Autodesk Fusion 360 part; units mm, degrees
(part 3 of 8)
sketch "SW1 support 1 profile" plane through (0, 0, 2) normal (0, 0, 1) x (1, 0, 0)
  line L0 (12.5897, 21.0158) -> (13.5897, 21.0158)
  line L1 (13.5897, 21.0158) -> (13.5897, 24.0158)
  line L2 (13.5897, 24.0158) -> (12.5897, 24.0158)
  line L3 (12.5897, 24.0158) -> (12.5897, 21.0158)
  dimension "d1946" = 12.5897
  dimension "d1947" = 21.0158
  dimension "d1948" = 1
  dimension "d1949" = 3
  constraint horizontal L0
  constraint vertical L1
  constraint horizontal L2
  constraint vertical L3
  measures "d1946" horizontal distance of origin L0.start
  measures "d1947" vertical distance of origin L0.start
  measures "d1948" distance of L0.start L0.end
  measures "d1949" distance of L0.end L1.end
extrude "SW1 support 1" add sketch "SW1 support 1 profile" along normal blind 14.2118 bodies 3
sketch "SW1 support 1 cap profile" plane through (0, -1.1931, 13.6376) normal (0, -0.087156, 0.996195) x (1, 0, 0)
  line L0 (12.4897, 21.7995) -> (13.6897, 21.7995)
  line L1 (13.6897, 21.7995) -> (13.6897, 25.7995)
  line L2 (13.6897, 25.7995) -> (12.4897, 25.7995)
  line L3 (12.4897, 25.7995) -> (12.4897, 21.7995)
  dimension "d1952" = 12.4897
  dimension "d1953" = 21.7995
  dimension "d1954" = 1.2
  dimension "d1955" = 4
  constraint horizontal L0
  constraint vertical L1
  constraint horizontal L2
  constraint vertical L3
  measures "d1952" horizontal distance of origin L0.start
  measures "d1953" vertical distance of origin L0.start
  measures "d1954" distance of L0.start L0.end
  measures "d1955" distance of L0.end L1.end
extrude "SW1 support 1 inclined cap" cut sketch "SW1 support 1 cap profile" along normal blind 39.0612 bodies 3
sketch "SW1 support 2 reinforced stem profile" plane through (0, 0, 2) normal (0, 0, 1) x (1, 0, 0)
  line L0 (16.8897, 20.0158) -> (19.2897, 20.0158)
  line L1 (19.2897, 20.0158) -> (19.2897, 25.0158)
  line L2 (19.2897, 25.0158) -> (16.8897, 25.0158)
  line L3 (16.8897, 25.0158) -> (16.8897, 20.0158)
  dimension "d1958" = 16.8897
  dimension "d1959" = 20.0158
  dimension "d1960" = 2.4
  dimension "d1961" = 5
  constraint horizontal L0
  constraint vertical L1
  constraint horizontal L2
  constraint vertical L3
  measures "d1958" horizontal distance of origin L0.start
  measures "d1959" vertical distance of origin L0.start
  measures "d1960" distance of L0.start L0.end
  measures "d1961" distance of L0.end L1.end
extrude "SW1 support 2 reinforced stem" add sketch "SW1 support 2 reinforced stem profile" along normal blind 11.7118 bodies 3
sketch "SW1 support 2 profile" plane through (0, 0, 2) normal (0, 0, 1) x (1, 0, 0)
  line L0 (17.5897, 21.0158) -> (18.5897, 21.0158)
  line L1 (18.5897, 21.0158) -> (18.5897, 24.0158)
  line L2 (18.5897, 24.0158) -> (17.5897, 24.0158)
  line L3 (17.5897, 24.0158) -> (17.5897, 21.0158)
  dimension "d1964" = 17.5897
  dimension "d1965" = 21.0158
  dimension "d1966" = 1
  dimension "d1967" = 3
  constraint horizontal L0
  constraint vertical L1
  constraint horizontal L2
  constraint vertical L3
  measures "d1964" horizontal distance of origin L0.start
  measures "d1965" vertical distance of origin L0.start
  measures "d1966" distance of L0.start L0.end
  measures "d1967" distance of L0.end L1.end
extrude "SW1 support 2" add sketch "SW1 support 2 profile" along normal blind 14.2118 bodies 3
sketch "SW1 support 2 cap profile" plane through (0, -1.1931, 13.6376) normal (0, -0.087156, 0.996195) x (1, 0, 0)
  line L0 (17.4897, 21.7995) -> (18.6897, 21.7995)
  line L1 (18.6897, 21.7995) -> (18.6897, 25.7995)
  line L2 (18.6897, 25.7995) -> (17.4897, 25.7995)
  line L3 (17.4897, 25.7995) -> (17.4897, 21.7995)
  dimension "d1970" = 17.4897
  dimension "d1971" = 21.7995
  dimension "d1972" = 1.2
  dimension "d1973" = 4
  constraint horizontal L0
  constraint vertical L1
  constraint horizontal L2
  constraint vertical L3
  measures "d1970" horizontal distance of origin L0.start
  measures "d1971" vertical distance of origin L0.start
  measures "d1972" distance of L0.start L0.end
  measures "d1973" distance of L0.end L1.end
extrude "SW1 support 2 inclined cap" cut sketch "SW1 support 2 cap profile" along normal blind 39.0612 bodies 3
sketch "SW2 receiver profile" plane through (0, -2.1431, 24.4961) normal (0, -0.087156, 0.996195) x (1, 0, 0)
  line L0 (30.8, 17.6972) -> (49.2, 17.6972)
  line L1 (49.2, 17.6972) -> (49.2, 35.2972)
  line L2 (49.2, 35.2972) -> (30.8, 35.2972)
  line L3 (30.8, 35.2972) -> (30.8, 17.6972)
  dimension "d1976" = 30.8
  dimension "d1977" = 17.6972
  dimension "d1978" = 18.4
  dimension "d1979" = 17.6
  constraint horizontal L0
  constraint vertical L1
  constraint horizontal L2
  constraint vertical L3
  measures "d1976" horizontal distance of origin L0.start
  measures "d1977" vertical distance of origin L0.start
  measures "d1978" distance of L0.start L0.end
  measures "d1979" distance of L0.end L1.end
extrude "SW2 integrated receiver" add sketch "SW2 receiver profile" against normal blind 11.5 bodies 2
sketch "SW2 switch lower clearance profile" plane through (0, -2.1431, 24.4961) normal (0, -0.087156, 0.996195) x (1, 0, 0)
  line L0 (32, 18.4972) -> (48, 18.4972)
  line L1 (48, 18.4972) -> (48, 34.4972)
  line L2 (48, 34.4972) -> (32, 34.4972)
  line L3 (32, 34.4972) -> (32, 18.4972)
  dimension "d1982" = 32
  dimension "d1983" = 18.4972
  dimension "d1984" = 16
  dimension "d1985" = 16
  constraint horizontal L0
  constraint vertical L1
  constraint horizontal L2
  constraint vertical L3
  measures "d1982" horizontal distance of origin L0.start
  measures "d1983" vertical distance of origin L0.start
  measures "d1984" distance of L0.start L0.end
  measures "d1985" distance of L0.end L1.end
extrude "SW2 switch lower clearance" cut sketch "SW2 switch lower clearance profile" against normal blind 5.5 bodies 2
sketch "SW2 holder pocket profile" plane through (0, -1.6638, 19.017) normal (0, -0.087156, 0.996195) x (1, 0, 0)
  line L0 (34.374, 19.925) -> (45.8055, 19.925)
  line L1 (45.8055, 19.925) -> (45.8055, 30.0741)
  line L2 (45.8055, 30.0741) -> (34.374, 30.0741)
  line L3 (34.374, 30.0741) -> (34.374, 19.925)
  dimension "d1988" = 34.374
  dimension "d1989" = 19.925
  dimension "d1990" = 11.4315
  dimension "d1991" = 10.1491
  constraint horizontal L0
  constraint vertical L1
  constraint horizontal L2
  constraint vertical L3
  measures "d1988" horizontal distance of origin L0.start
  measures "d1989" vertical distance of origin L0.start
  measures "d1990" distance of L0.start L0.end
  measures "d1991" distance of L0.end L1.end
extrude "SW2 open-bottom holder pocket" cut sketch "SW2 holder pocket profile" against normal blind 6.2 bodies 2
sketch "SW2 spring 1 release 1 profile" plane through (0, -2.056, 23.4999) normal (0, -0.087156, 0.996195) x (1, 0, 0)
  line L0 (30.7897, 27.0995) -> (34.374, 27.0995)
  line L1 (34.374, 27.0995) -> (34.374, 27.6995)
  line L2 (34.374, 27.6995) -> (30.7897, 27.6995)
  line L3 (30.7897, 27.6995) -> (30.7897, 27.0995)
  dimension "d1994" = 30.7897
  dimension "d1995" = 27.0995
  dimension "d1996" = 3.5843
  dimension "d1997" = 0.6
  constraint horizontal L0
  constraint vertical L1
  constraint horizontal L2
  constraint vertical L3
  measures "d1994" horizontal distance of origin L0.start
  measures "d1995" vertical distance of origin L0.start
  measures "d1996" distance of L0.start L0.end
  measures "d1997" distance of L0.end L1.end
extrude "SW2 spring 1 release 1" cut sketch "SW2 spring 1 release 1 profile" against normal blind 10.7 bodies 2
sketch "SW2 spring 1 release 2 profile" plane through (0, -2.056, 23.4999) normal (0, -0.087156, 0.996195) x (1, 0, 0)
  line L0 (30.7897, 29.6995) -> (34.374, 29.6995)
  line L1 (34.374, 29.6995) -> (34.374, 30.2995)
  line L2 (34.374, 30.2995) -> (30.7897, 30.2995)
  line L3 (30.7897, 30.2995) -> (30.7897, 29.6995)
  dimension "d2000" = 30.7897
  dimension "d2001" = 29.6995
  dimension "d2002" = 3.5843
  dimension "d2003" = 0.6
  constraint horizontal L0
  constraint vertical L1
  constraint horizontal L2
  constraint vertical L3
  measures "d2000" horizontal distance of origin L0.start
  measures "d2001" vertical distance of origin L0.start
  measures "d2002" distance of L0.start L0.end
  measures "d2003" distance of L0.end L1.end
extrude "SW2 spring 1 release 2" cut sketch "SW2 spring 1 release 2 profile" against normal blind 10.7 bodies 2
sketch "SW2 spring 1 inner clearance profile" plane through (0, -1.6638, 19.017) normal (0, -0.087156, 0.996195) x (1, 0, 0)
  line L0 (31.6897, 27.6995) -> (34.374, 27.6995)
  line L1 (34.374, 27.6995) -> (34.374, 29.6995)
  line L2 (34.374, 29.6995) -> (31.6897, 29.6995)
  line L3 (31.6897, 29.6995) -> (31.6897, 27.6995)
  dimension "d2006" = 31.6897
  dimension "d2007" = 27.6995
  dimension "d2008" = 2.6843
  dimension "d2009" = 2
  constraint horizontal L0
  constraint vertical L1
  constraint horizontal L2
  constraint vertical L3
  measures "d2006" horizontal distance of origin L0.start
  measures "d2007" vertical distance of origin L0.start
  measures "d2008" distance of L0.start L0.end
  measures "d2009" distance of L0.end L1.end
extrude "SW2 spring 1 inner clearance" cut sketch "SW2 spring 1 inner clearance profile" against normal blind 6.2 bodies 2
sketch "SW2 spring 1 hook profile" plane through (0, -1.2106, 13.8368) normal (0, -0.087156, 0.996195) x (1, 0, 0)
  line L0 (30.8897, 27.6995) -> (34.874, 27.6995)
  line L1 (34.874, 27.6995) -> (34.874, 29.6995)
  line L2 (34.874, 29.6995) -> (30.8897, 29.6995)
  line L3 (30.8897, 29.6995) -> (30.8897, 27.6995)
  dimension "d2012" = 30.8897
  dimension "d2013" = 27.6995
  dimension "d2014" = 3.9843
  dimension "d2015" = 2
  constraint horizontal L0
  constraint vertical L1
  constraint horizontal L2
  constraint vertical L3
  measures "d2012" horizontal distance of origin L0.start
  measures "d2013" vertical distance of origin L0.start
  measures "d2014" distance of L0.start L0.end
  measures "d2015" distance of L0.end L1.end
extrude "SW2 spring 1 retaining hook" add sketch "SW2 spring 1 hook profile" against normal blind 0.8 bodies 2
chamfer "SW2 spring 1 45 degree lead-in" distance 0.35 angle 45 1 edges at (34.874, 27.4495, 15.5412) tangent chain off on bodies 2
sketch "SW2 spring 2 release 1 profile" plane through (0, -2.056, 23.4999) normal (0, -0.087156, 0.996195) x (1, 0, 0)
  line L0 (45.8055, 27.0995) -> (49.3897, 27.0995)
  line L1 (49.3897, 27.0995) -> (49.3897, 27.6995)
  line L2 (49.3897, 27.6995) -> (45.8055, 27.6995)
  line L3 (45.8055, 27.6995) -> (45.8055, 27.0995)
  dimension "d2019" = 45.8055
  dimension "d2020" = 27.0995
  dimension "d2021" = 3.5843
  dimension "d2022" = 0.6
  constraint horizontal L0
  constraint vertical L1
  constraint horizontal L2
  constraint vertical L3
  measures "d2019" horizontal distance of origin L0.start
  measures "d2020" vertical distance of origin L0.start
  measures "d2021" distance of L0.start L0.end
  measures "d2022" distance of L0.end L1.end
extrude "SW2 spring 2 release 1" cut sketch "SW2 spring 2 release 1 profile" against normal blind 10.7 bodies 2
sketch "SW2 spring 2 release 2 profile" plane through (0, -2.056, 23.4999) normal (0, -0.087156, 0.996195) x (1, 0, 0)
  line L0 (45.8055, 29.6995) -> (49.3897, 29.6995)
  line L1 (49.3897, 29.6995) -> (49.3897, 30.2995)
  line L2 (49.3897, 30.2995) -> (45.8055, 30.2995)
  line L3 (45.8055, 30.2995) -> (45.8055, 29.6995)
  dimension "d2025" = 45.8055
  dimension "d2026" = 29.6995
  dimension "d2027" = 3.5843
  dimension "d2028" = 0.6
  constraint horizontal L0
  constraint vertical L1
  constraint horizontal L2
  constraint vertical L3
  measures "d2025" horizontal distance of origin L0.start
  measures "d2026" vertical distance of origin L0.start
  measures "d2027" distance of L0.start L0.end
  measures "d2028" distance of L0.end L1.end
extrude "SW2 spring 2 release 2" cut sketch "SW2 spring 2 release 2 profile" against normal blind 10.7 bodies 2
sketch "SW2 spring 2 inner clearance profile" plane through (0, -1.6638, 19.017) normal (0, -0.087156, 0.996195) x (1, 0, 0)
  line L0 (45.8055, 27.6995) -> (48.4897, 27.6995)
  line L1 (48.4897, 27.6995) -> (48.4897, 29.6995)
  line L2 (48.4897, 29.6995) -> (45.8055, 29.6995)
  line L3 (45.8055, 29.6995) -> (45.8055, 27.6995)
  dimension "d2031" = 45.8055
  dimension "d2032" = 27.6995
  dimension "d2033" = 2.6843
  dimension "d2034" = 2
  constraint horizontal L0
  constraint vertical L1
  constraint horizontal L2
  constraint vertical L3
  measures "d2031" horizontal distance of origin L0.start
  measures "d2032" vertical distance of origin L0.start
  measures "d2033" distance of L0.start L0.end
  measures "d2034" distance of L0.end L1.end
extrude "SW2 spring 2 inner clearance" cut sketch "SW2 spring 2 inner clearance profile" against normal blind 6.2 bodies 2
sketch "SW2 spring 2 hook profile" plane through (0, -1.2106, 13.8368) normal (0, -0.087156, 0.996195) x (1, 0, 0)
  line L0 (45.3055, 27.6995) -> (49.2897, 27.6995)
  line L1 (49.2897, 27.6995) -> (49.2897, 29.6995)
  line L2 (49.2897, 29.6995) -> (45.3055, 29.6995)
  line L3 (45.3055, 29.6995) -> (45.3055, 27.6995)
  dimension "d2037" = 45.3055
  dimension "d2038" = 27.6995
  dimension "d2039" = 3.9843
  dimension "d2040" = 2
  constraint horizontal L0
  constraint vertical L1
  constraint horizontal L2
  constraint vertical L3
  measures "d2037" horizontal distance of origin L0.start
  measures "d2038" vertical distance of origin L0.start
  measures "d2039" distance of L0.start L0.end
  measures "d2040" distance of L0.end L1.end
extrude "SW2 spring 2 retaining hook" add sketch "SW2 spring 2 hook profile" against normal blind 0.8 bodies 2
chamfer "SW2 spring 2 45 degree lead-in" distance 0.35 angle 45 1 edges at (45.3055, 27.4495, 15.5412) tangent chain off on bodies 2
sketch "SW2 upper stop 1 profile" plane through (0, -1.6638, 19.017) normal (0, -0.087156, 0.996195) x (1, 0, 0)
  line L0 (36.5897, 28.9995) -> (37.5897, 28.9995)
  line L1 (37.5897, 28.9995) -> (37.5897, 33.7995)
  line L2 (37.5897, 33.7995) -> (36.5897, 33.7995)
  line L3 (36.5897, 33.7995) -> (36.5897, 28.9995)
  dimension "d2044" = 36.5897
  dimension "d2045" = 28.9995
  dimension "d2046" = 1
  dimension "d2047" = 4.8
  constraint horizontal L0
  constraint vertical L1
  constraint horizontal L2
  constraint vertical L3
  measures "d2044" horizontal distance of origin L0.start
  measures "d2045" vertical distance of origin L0.start
  measures "d2046" distance of L0.start L0.end
  measures "d2047" distance of L0.end L1.end
extrude "SW2 upper stop 1" add sketch "SW2 upper stop 1 profile" along normal blind 0.8 bodies 2
sketch "SW2 upper stop 2 profile" plane through (0, -1.6638, 19.017) normal (0, -0.087156, 0.996195) x (1, 0, 0)
  line L0 (42.5897, 28.9995) -> (43.5897, 28.9995)
  line L1 (43.5897, 28.9995) -> (43.5897, 33.7995)
  line L2 (43.5897, 33.7995) -> (42.5897, 33.7995)
  line L3 (42.5897, 33.7995) -> (42.5897, 28.9995)
  dimension "d2050" = 42.5897
  dimension "d2051" = 28.9995
  dimension "d2052" = 1
  dimension "d2053" = 4.8
  constraint horizontal L0
  constraint vertical L1
  constraint horizontal L2
  constraint vertical L3
  measures "d2050" horizontal distance of origin L0.start
  measures "d2051" vertical distance of origin L0.start
  measures "d2052" distance of L0.start L0.end
  measures "d2053" distance of L0.end L1.end
extrude "SW2 upper stop 2" add sketch "SW2 upper stop 2 profile" along normal blind 0.8 bodies 2
sketch "SW2 wire exit 1 profile" plane through (0, -1.5592, 17.8216) normal (0, -0.087156, 0.996195) x (1, 0, 0)
  line L0 (30.7897, 19.8995) -> (34.574, 19.8995)
  line L1 (34.574, 19.8995) -> (34.574, 27.6995)
  line L2 (34.574, 27.6995) -> (30.7897, 27.6995)
  line L3 (30.7897, 27.6995) -> (30.7897, 19.8995)
  dimension "d2056" = 30.7897
  dimension "d2057" = 19.8995
  dimension "d2058" = 3.7843
  dimension "d2059" = 7.8
  constraint horizontal L0
  constraint vertical L1
  constraint horizontal L2
  constraint vertical L3
  measures "d2056" horizontal distance of origin L0.start
  measures "d2057" vertical distance of origin L0.start
  measures "d2058" distance of L0.start L0.end
  measures "d2059" distance of L0.end L1.end
extrude "SW2 wire exit 1" cut sketch "SW2 wire exit 1 profile" against normal blind 5 bodies 2
sketch "SW2 wire exit 2 profile" plane through (0, -1.5592, 17.8216) normal (0, -0.087156, 0.996195) x (1, 0, 0)
  line L0 (45.6055, 19.8995) -> (49.3897, 19.8995)
  line L1 (49.3897, 19.8995) -> (49.3897, 27.6995)
  line L2 (49.3897, 27.6995) -> (45.6055, 27.6995)
  line L3 (45.6055, 27.6995) -> (45.6055, 19.8995)
  dimension "d2062" = 45.6055
  dimension "d2063" = 19.8995
  dimension "d2064" = 3.7843
  dimension "d2065" = 7.8
  constraint horizontal L0
  constraint vertical L1
  constraint horizontal L2
  constraint vertical L3
  measures "d2062" horizontal distance of origin L0.start
  measures "d2063" vertical distance of origin L0.start
  measures "d2064" distance of L0.start L0.end
  measures "d2065" distance of L0.end L1.end
extrude "SW2 wire exit 2" cut sketch "SW2 wire exit 2 profile" against normal blind 5 bodies 2
sketch "SW2 support 1 reinforced stem profile" plane through (0, 0, 2) normal (0, 0, 1) x (1, 0, 0)
  line L0 (36.3897, 20.0158) -> (38.7897, 20.0158)
  line L1 (38.7897, 20.0158) -> (38.7897, 25.0158)
  line L2 (38.7897, 25.0158) -> (36.3897, 25.0158)
  line L3 (36.3897, 25.0158) -> (36.3897, 20.0158)
  dimension "d2068" = 36.3897
  dimension "d2069" = 20.0158
  dimension "d2070" = 2.4
  dimension "d2071" = 5
  constraint horizontal L0
  constraint vertical L1
  constraint horizontal L2
  constraint vertical L3
  measures "d2068" horizontal distance of origin L0.start
  measures "d2069" vertical distance of origin L0.start
  measures "d2070" distance of L0.start L0.end
  measures "d2071" distance of L0.end L1.end
extrude "SW2 support 1 reinforced stem" add sketch "SW2 support 1 reinforced stem profile" along normal blind 11.7118 bodies 3
sketch "SW2 support 1 profile" plane through (0, 0, 2) normal (0, 0, 1) x (1, 0, 0)
  line L0 (37.0897, 21.0158) -> (38.0897, 21.0158)
  line L1 (38.0897, 21.0158) -> (38.0897, 24.0158)
  line L2 (38.0897, 24.0158) -> (37.0897, 24.0158)
  line L3 (37.0897, 24.0158) -> (37.0897, 21.0158)
  dimension "d2074" = 37.0897
  dimension "d2075" = 21.0158
  dimension "d2076" = 1
  dimension "d2077" = 3
  constraint horizontal L0
  constraint vertical L1
  constraint horizontal L2
  constraint vertical L3
  measures "d2074" horizontal distance of origin L0.start
  measures "d2075" vertical distance of origin L0.start
  measures "d2076" distance of L0.start L0.end
  measures "d2077" distance of L0.end L1.end
extrude "SW2 support 1" add sketch "SW2 support 1 profile" along normal blind 14.2118 bodies 3
sketch "SW2 support 1 cap profile" plane through (0, -1.1931, 13.6376) normal (0, -0.087156, 0.996195) x (1, 0, 0)
  line L0 (36.9897, 21.7995) -> (38.1897, 21.7995)
  line L1 (38.1897, 21.7995) -> (38.1897, 25.7995)
  line L2 (38.1897, 25.7995) -> (36.9897, 25.7995)
  line L3 (36.9897, 25.7995) -> (36.9897, 21.7995)
  dimension "d2080" = 36.9897
  dimension "d2081" = 21.7995
  dimension "d2082" = 1.2
  dimension "d2083" = 4
  constraint horizontal L0
  constraint vertical L1
  constraint horizontal L2
  constraint vertical L3
  measures "d2080" horizontal distance of origin L0.start
  measures "d2081" vertical distance of origin L0.start
  measures "d2082" distance of L0.start L0.end
  measures "d2083" distance of L0.end L1.end
extrude "SW2 support 1 inclined cap" cut sketch "SW2 support 1 cap profile" along normal blind 39.0612 bodies 3
sketch "SW2 support 2 reinforced stem profile" plane through (0, 0, 2) normal (0, 0, 1) x (1, 0, 0)
  line L0 (41.3897, 20.0158) -> (43.7897, 20.0158)
  line L1 (43.7897, 20.0158) -> (43.7897, 25.0158)
  line L2 (43.7897, 25.0158) -> (41.3897, 25.0158)
  line L3 (41.3897, 25.0158) -> (41.3897, 20.0158)
  dimension "d2086" = 41.3897
  dimension "d2087" = 20.0158
  dimension "d2088" = 2.4
  dimension "d2089" = 5
  constraint horizontal L0
  constraint vertical L1
  constraint horizontal L2
  constraint vertical L3
  measures "d2086" horizontal distance of origin L0.start
  measures "d2087" vertical distance of origin L0.start
  measures "d2088" distance of L0.start L0.end
  measures "d2089" distance of L0.end L1.end
extrude "SW2 support 2 reinforced stem" add sketch "SW2 support 2 reinforced stem profile" along normal blind 11.7118 bodies 3
sketch "SW2 support 2 profile" plane through (0, 0, 2) normal (0, 0, 1) x (1, 0, 0)
  line L0 (42.0897, 21.0158) -> (43.0897, 21.0158)
  line L1 (43.0897, 21.0158) -> (43.0897, 24.0158)
  line L2 (43.0897, 24.0158) -> (42.0897, 24.0158)
  line L3 (42.0897, 24.0158) -> (42.0897, 21.0158)
  dimension "d2092" = 42.0897
  dimension "d2093" = 21.0158
  dimension "d2094" = 1
  dimension "d2095" = 3
  constraint horizontal L0
  constraint vertical L1
  constraint horizontal L2
  constraint vertical L3
  measures "d2092" horizontal distance of origin L0.start
  measures "d2093" vertical distance of origin L0.start
  measures "d2094" distance of L0.start L0.end
  measures "d2095" distance of L0.end L1.end
extrude "SW2 support 2" add sketch "SW2 support 2 profile" along normal blind 14.2118 bodies 3
sketch "SW2 support 2 cap profile" plane through (0, -1.1931, 13.6376) normal (0, -0.087156, 0.996195) x (1, 0, 0)
  line L0 (41.9897, 21.7995) -> (43.1897, 21.7995)
  line L1 (43.1897, 21.7995) -> (43.1897, 25.7995)
  line L2 (43.1897, 25.7995) -> (41.9897, 25.7995)
  line L3 (41.9897, 25.7995) -> (41.9897, 21.7995)
  dimension "d2098" = 41.9897
  dimension "d2099" = 21.7995
  dimension "d2100" = 1.2
  dimension "d2101" = 4
  constraint horizontal L0
  constraint vertical L1
  constraint horizontal L2
  constraint vertical L3
  measures "d2098" horizontal distance of origin L0.start
  measures "d2099" vertical distance of origin L0.start
  measures "d2100" distance of L0.start L0.end
  measures "d2101" distance of L0.end L1.end
extrude "SW2 support 2 inclined cap" cut sketch "SW2 support 2 cap profile" along normal blind 39.0612 bodies 3
sketch "SW3 receiver profile" plane through (0, -2.1431, 24.4961) normal (0, -0.087156, 0.996195) x (1, 0, 0)
  line L0 (55.3, 17.6972) -> (73.7, 17.6972)
  line L1 (73.7, 17.6972) -> (73.7, 35.2972)
  line L2 (73.7, 35.2972) -> (55.3, 35.2972)
  line L3 (55.3, 35.2972) -> (55.3, 17.6972)
  dimension "d2104" = 55.3
  dimension "d2105" = 17.6972
  dimension "d2106" = 18.4
  dimension "d2107" = 17.6
  constraint horizontal L0
  constraint vertical L1
  constraint horizontal L2
  constraint vertical L3
  measures "d2104" horizontal distance of origin L0.start
  measures "d2105" vertical distance of origin L0.start
  measures "d2106" distance of L0.start L0.end
  measures "d2107" distance of L0.end L1.end
extrude "SW3 integrated receiver" add sketch "SW3 receiver profile" against normal blind 11.5 bodies 2
sketch "SW3 switch lower clearance profile" plane through (0, -2.1431, 24.4961) normal (0, -0.087156, 0.996195) x (1, 0, 0)
  line L0 (56.5, 18.4972) -> (72.5, 18.4972)
  line L1 (72.5, 18.4972) -> (72.5, 34.4972)
  line L2 (72.5, 34.4972) -> (56.5, 34.4972)
  line L3 (56.5, 34.4972) -> (56.5, 18.4972)
  dimension "d2110" = 56.5
  dimension "d2111" = 18.4972
  dimension "d2112" = 16
  dimension "d2113" = 16
  constraint horizontal L0
  constraint vertical L1
  constraint horizontal L2
  constraint vertical L3
  measures "d2110" horizontal distance of origin L0.start
  measures "d2111" vertical distance of origin L0.start
  measures "d2112" distance of L0.start L0.end
  measures "d2113" distance of L0.end L1.end
extrude "SW3 switch lower clearance" cut sketch "SW3 switch lower clearance profile" against normal blind 5.5 bodies 2
sketch "SW3 holder pocket profile" plane through (0, -1.6638, 19.017) normal (0, -0.087156, 0.996195) x (1, 0, 0)
  line L0 (58.874, 19.925) -> (70.3055, 19.925)
  line L1 (70.3055, 19.925) -> (70.3055, 30.0741)
  line L2 (70.3055, 30.0741) -> (58.874, 30.0741)
  line L3 (58.874, 30.0741) -> (58.874, 19.925)
  dimension "d2116" = 58.874
  dimension "d2117" = 19.925
  dimension "d2118" = 11.4315
  dimension "d2119" = 10.1491
  constraint horizontal L0
  constraint vertical L1
  constraint horizontal L2
  constraint vertical L3
  measures "d2116" horizontal distance of origin L0.start
  measures "d2117" vertical distance of origin L0.start
  measures "d2118" distance of L0.start L0.end
  measures "d2119" distance of L0.end L1.end
extrude "SW3 open-bottom holder pocket" cut sketch "SW3 holder pocket profile" against normal blind 6.2 bodies 2
sketch "SW3 spring 1 release 1 profile" plane through (0, -2.056, 23.4999) normal (0, -0.087156, 0.996195) x (1, 0, 0)
  line L0 (55.2897, 27.0995) -> (58.874, 27.0995)
  line L1 (58.874, 27.0995) -> (58.874, 27.6995)
  line L2 (58.874, 27.6995) -> (55.2897, 27.6995)
  line L3 (55.2897, 27.6995) -> (55.2897, 27.0995)
  dimension "d2122" = 55.2897
  dimension "d2123" = 27.0995
  dimension "d2124" = 3.5843
  dimension "d2125" = 0.6
  constraint horizontal L0
  constraint vertical L1
  constraint horizontal L2
  constraint vertical L3
  measures "d2122" horizontal distance of origin L0.start
  measures "d2123" vertical distance of origin L0.start
  measures "d2124" distance of L0.start L0.end
  measures "d2125" distance of L0.end L1.end
extrude "SW3 spring 1 release 1" cut sketch "SW3 spring 1 release 1 profile" against normal blind 10.7 bodies 2
sketch "SW3 spring 1 release 2 profile" plane through (0, -2.056, 23.4999) normal (0, -0.087156, 0.996195) x (1, 0, 0)
  line L0 (55.2897, 29.6995) -> (58.874, 29.6995)
  line L1 (58.874, 29.6995) -> (58.874, 30.2995)
  line L2 (58.874, 30.2995) -> (55.2897, 30.2995)
  line L3 (55.2897, 30.2995) -> (55.2897, 29.6995)
  dimension "d2128" = 55.2897
  dimension "d2129" = 29.6995
  dimension "d2130" = 3.5843
  dimension "d2131" = 0.6
  constraint horizontal L0
  constraint vertical L1
  constraint horizontal L2
  constraint vertical L3
  measures "d2128" horizontal distance of origin L0.start
  measures "d2129" vertical distance of origin L0.start
  measures "d2130" distance of L0.start L0.end
  measures "d2131" distance of L0.end L1.end
extrude "SW3 spring 1 release 2" cut sketch "SW3 spring 1 release 2 profile" against normal blind 10.7 bodies 2
sketch "SW3 spring 1 inner clearance profile" plane through (0, -1.6638, 19.017) normal (0, -0.087156, 0.996195) x (1, 0, 0)
  line L0 (56.1897, 27.6995) -> (58.874, 27.6995)
  line L1 (58.874, 27.6995) -> (58.874, 29.6995)
  line L2 (58.874, 29.6995) -> (56.1897, 29.6995)
  line L3 (56.1897, 29.6995) -> (56.1897, 27.6995)
  dimension "d2134" = 56.1897
  dimension "d2135" = 27.6995
  dimension "d2136" = 2.6843
  dimension "d2137" = 2
  constraint horizontal L0
  constraint vertical L1
  constraint horizontal L2
  constraint vertical L3
  measures "d2134" horizontal distance of origin L0.start
  measures "d2135" vertical distance of origin L0.start
  measures "d2136" distance of L0.start L0.end
  measures "d2137" distance of L0.end L1.end
extrude "SW3 spring 1 inner clearance" cut sketch "SW3 spring 1 inner clearance profile" against normal blind 6.2 bodies 2
sketch "SW3 spring 1 hook profile" plane through (0, -1.2106, 13.8368) normal (0, -0.087156, 0.996195) x (1, 0, 0)
  line L0 (55.3897, 27.6995) -> (59.374, 27.6995)
  line L1 (59.374, 27.6995) -> (59.374, 29.6995)
  line L2 (59.374, 29.6995) -> (55.3897, 29.6995)
  line L3 (55.3897, 29.6995) -> (55.3897, 27.6995)
  dimension "d2140" = 55.3897
  dimension "d2141" = 27.6995
  dimension "d2142" = 3.9843
  dimension "d2143" = 2
  constraint horizontal L0
  constraint vertical L1
  constraint horizontal L2
  constraint vertical L3
  measures "d2140" horizontal distance of origin L0.start
  measures "d2141" vertical distance of origin L0.start
  measures "d2142" distance of L0.start L0.end
  measures "d2143" distance of L0.end L1.end
extrude "SW3 spring 1 retaining hook" add sketch "SW3 spring 1 hook profile" against normal blind 0.8 bodies 2
chamfer "SW3 spring 1 45 degree lead-in" distance 0.35 angle 45 1 edges at (59.374, 27.4495, 15.5412) tangent chain off on bodies 2
sketch "SW3 spring 2 release 1 profile" plane through (0, -2.056, 23.4999) normal (0, -0.087156, 0.996195) x (1, 0, 0)
  line L0 (70.3055, 27.0995) -> (73.8897, 27.0995)
  line L1 (73.8897, 27.0995) -> (73.8897, 27.6995)
  line L2 (73.8897, 27.6995) -> (70.3055, 27.6995)
  line L3 (70.3055, 27.6995) -> (70.3055, 27.0995)
  dimension "d2147" = 70.3055
  dimension "d2148" = 27.0995
  dimension "d2149" = 3.5843
  dimension "d2150" = 0.6
  constraint horizontal L0
  constraint vertical L1
  constraint horizontal L2
  constraint vertical L3
  measures "d2147" horizontal distance of origin L0.start
  measures "d2148" vertical distance of origin L0.start
  measures "d2149" distance of L0.start L0.end
  measures "d2150" distance of L0.end L1.end
extrude "SW3 spring 2 release 1" cut sketch "SW3 spring 2 release 1 profile" against normal blind 10.7 bodies 2
sketch "SW3 spring 2 release 2 profile" plane through (0, -2.056, 23.4999) normal (0, -0.087156, 0.996195) x (1, 0, 0)
  line L0 (70.3055, 29.6995) -> (73.8897, 29.6995)
  line L1 (73.8897, 29.6995) -> (73.8897, 30.2995)
  line L2 (73.8897, 30.2995) -> (70.3055, 30.2995)
  line L3 (70.3055, 30.2995) -> (70.3055, 29.6995)
  dimension "d2153" = 70.3055
  dimension "d2154" = 29.6995
  dimension "d2155" = 3.5843
  dimension "d2156" = 0.6
  constraint horizontal L0
  constraint vertical L1
  constraint horizontal L2
  constraint vertical L3
  measures "d2153" horizontal distance of origin L0.start
  measures "d2154" vertical distance of origin L0.start
  measures "d2155" distance of L0.start L0.end
  measures "d2156" distance of L0.end L1.end
extrude "SW3 spring 2 release 2" cut sketch "SW3 spring 2 release 2 profile" against normal blind 10.7 bodies 2
sketch "SW3 spring 2 inner clearance profile" plane through (0, -1.6638, 19.017) normal (0, -0.087156, 0.996195) x (1, 0, 0)
  line L0 (70.3055, 27.6995) -> (72.9897, 27.6995)
  line L1 (72.9897, 27.6995) -> (72.9897, 29.6995)
  line L2 (72.9897, 29.6995) -> (70.3055, 29.6995)
  line L3 (70.3055, 29.6995) -> (70.3055, 27.6995)
  dimension "d2159" = 70.3055
  dimension "d2160" = 27.6995
  dimension "d2161" = 2.6843
  dimension "d2162" = 2
  constraint horizontal L0
  constraint vertical L1
  constraint horizontal L2
  constraint vertical L3
  measures "d2159" horizontal distance of origin L0.start
  measures "d2160" vertical distance of origin L0.start
  measures "d2161" distance of L0.start L0.end
  measures "d2162" distance of L0.end L1.end
extrude "SW3 spring 2 inner clearance" cut sketch "SW3 spring 2 inner clearance profile" against normal blind 6.2 bodies 2
sketch "SW3 spring 2 hook profile" plane through (0, -1.2106, 13.8368) normal (0, -0.087156, 0.996195) x (1, 0, 0)
  line L0 (69.8055, 27.6995) -> (73.7897, 27.6995)
  line L1 (73.7897, 27.6995) -> (73.7897, 29.6995)
  line L2 (73.7897, 29.6995) -> (69.8055, 29.6995)
  line L3 (69.8055, 29.6995) -> (69.8055, 27.6995)
  dimension "d2165" = 69.8055
  dimension "d2166" = 27.6995
  dimension "d2167" = 3.9843
  dimension "d2168" = 2
  constraint horizontal L0
  constraint vertical L1
  constraint horizontal L2
  constraint vertical L3
  measures "d2165" horizontal distance of origin L0.start
  measures "d2166" vertical distance of origin L0.start
  measures "d2167" distance of L0.start L0.end
  measures "d2168" distance of L0.end L1.end
extrude "SW3 spring 2 retaining hook" add sketch "SW3 spring 2 hook profile" against normal blind 0.8 bodies 2
chamfer "SW3 spring 2 45 degree lead-in" distance 0.35 angle 45 1 edges at (69.8055, 27.4495, 15.5412) tangent chain off on bodies 2
sketch "SW3 upper stop 1 profile" plane through (0, -1.6638, 19.017) normal (0, -0.087156, 0.996195) x (1, 0, 0)
  line L0 (61.0897, 28.9995) -> (62.0897, 28.9995)
  line L1 (62.0897, 28.9995) -> (62.0897, 33.7995)
  line L2 (62.0897, 33.7995) -> (61.0897, 33.7995)
  line L3 (61.0897, 33.7995) -> (61.0897, 28.9995)
  dimension "d2172" = 61.0897
  dimension "d2173" = 28.9995
  dimension "d2174" = 1
  dimension "d2175" = 4.8
  constraint horizontal L0
  constraint vertical L1
  constraint horizontal L2
  constraint vertical L3
  measures "d2172" horizontal distance of origin L0.start
  measures "d2173" vertical distance of origin L0.start
  measures "d2174" distance of L0.start L0.end
  measures "d2175" distance of L0.end L1.end
extrude "SW3 upper stop 1" add sketch "SW3 upper stop 1 profile" along normal blind 0.8 bodies 2
sketch "SW3 upper stop 2 profile" plane through (0, -1.6638, 19.017) normal (0, -0.087156, 0.996195) x (1, 0, 0)
  line L0 (67.0897, 28.9995) -> (68.0897, 28.9995)
  line L1 (68.0897, 28.9995) -> (68.0897, 33.7995)
  line L2 (68.0897, 33.7995) -> (67.0897, 33.7995)
  line L3 (67.0897, 33.7995) -> (67.0897, 28.9995)
  dimension "d2178" = 67.0897
  dimension "d2179" = 28.9995
  dimension "d2180" = 1
  dimension "d2181" = 4.8
  constraint horizontal L0
  constraint vertical L1
  constraint horizontal L2
  constraint vertical L3
  measures "d2178" horizontal distance of origin L0.start
  measures "d2179" vertical distance of origin L0.start
  measures "d2180" distance of L0.start L0.end
  measures "d2181" distance of L0.end L1.end
extrude "SW3 upper stop 2" add sketch "SW3 upper stop 2 profile" along normal blind 0.8 bodies 2
sketch "SW3 wire exit 1 profile" plane through (0, -1.5592, 17.8216) normal (0, -0.087156, 0.996195) x (1, 0, 0)
  line L0 (55.2897, 19.8995) -> (59.074, 19.8995)
  line L1 (59.074, 19.8995) -> (59.074, 27.6995)
  line L2 (59.074, 27.6995) -> (55.2897, 27.6995)
  line L3 (55.2897, 27.6995) -> (55.2897, 19.8995)
  dimension "d2184" = 55.2897
  dimension "d2185" = 19.8995
  dimension "d2186" = 3.7843
  dimension "d2187" = 7.8
  constraint horizontal L0
  constraint vertical L1
  constraint horizontal L2
  constraint vertical L3
  measures "d2184" horizontal distance of origin L0.start
  measures "d2185" vertical distance of origin L0.start
  measures "d2186" distance of L0.start L0.end
  measures "d2187" distance of L0.end L1.end
extrude "SW3 wire exit 1" cut sketch "SW3 wire exit 1 profile" against normal blind 5 bodies 2
sketch "SW3 wire exit 2 profile" plane through (0, -1.5592, 17.8216) normal (0, -0.087156, 0.996195) x (1, 0, 0)
  line L0 (70.1055, 19.8995) -> (73.8897, 19.8995)
  line L1 (73.8897, 19.8995) -> (73.8897, 27.6995)
  line L2 (73.8897, 27.6995) -> (70.1055, 27.6995)
  line L3 (70.1055, 27.6995) -> (70.1055, 19.8995)
  dimension "d2190" = 70.1055
  dimension "d2191" = 19.8995
  dimension "d2192" = 3.7843
  dimension "d2193" = 7.8
  constraint horizontal L0
  constraint vertical L1
  constraint horizontal L2
  constraint vertical L3
  measures "d2190" horizontal distance of origin L0.start
  measures "d2191" vertical distance of origin L0.start
  measures "d2192" distance of L0.start L0.end
  measures "d2193" distance of L0.end L1.end
extrude "SW3 wire exit 2" cut sketch "SW3 wire exit 2 profile" against normal blind 5 bodies 2
sketch "SW3 support 1 reinforced stem profile" plane through (0, 0, 2) normal (0, 0, 1) x (1, 0, 0)
  line L0 (60.8897, 20.0158) -> (63.2897, 20.0158)
  line L1 (63.2897, 20.0158) -> (63.2897, 25.0158)
  line L2 (63.2897, 25.0158) -> (60.8897, 25.0158)
  line L3 (60.8897, 25.0158) -> (60.8897, 20.0158)
  dimension "d2196" = 60.8897
  dimension "d2197" = 20.0158
  dimension "d2198" = 2.4
  dimension "d2199" = 5
  constraint horizontal L0
  constraint vertical L1
  constraint horizontal L2
  constraint vertical L3
  measures "d2196" horizontal distance of origin L0.start
  measures "d2197" vertical distance of origin L0.start
  measures "d2198" distance of L0.start L0.end
  measures "d2199" distance of L0.end L1.end
extrude "SW3 support 1 reinforced stem" add sketch "SW3 support 1 reinforced stem profile" along normal blind 11.7118 bodies 3
sketch "SW3 support 1 profile" plane through (0, 0, 2) normal (0, 0, 1) x (1, 0, 0)
  line L0 (61.5897, 21.0158) -> (62.5897, 21.0158)
  line L1 (62.5897, 21.0158) -> (62.5897, 24.0158)
  line L2 (62.5897, 24.0158) -> (61.5897, 24.0158)
  line L3 (61.5897, 24.0158) -> (61.5897, 21.0158)
  dimension "d2202" = 61.5897
  dimension "d2203" = 21.0158
  dimension "d2204" = 1
  dimension "d2205" = 3
  constraint horizontal L0
  constraint vertical L1
  constraint horizontal L2
  constraint vertical L3
  measures "d2202" horizontal distance of origin L0.start
  measures "d2203" vertical distance of origin L0.start
  measures "d2204" distance of L0.start L0.end
  measures "d2205" distance of L0.end L1.end
extrude "SW3 support 1" add sketch "SW3 support 1 profile" along normal blind 14.2118 bodies 3
sketch "SW3 support 1 cap profile" plane through (0, -1.1931, 13.6376) normal (0, -0.087156, 0.996195) x (1, 0, 0)
  line L0 (61.4897, 21.7995) -> (62.6897, 21.7995)
  line L1 (62.6897, 21.7995) -> (62.6897, 25.7995)
  line L2 (62.6897, 25.7995) -> (61.4897, 25.7995)
  line L3 (61.4897, 25.7995) -> (61.4897, 21.7995)
  dimension "d2208" = 61.4897
  dimension "d2209" = 21.7995
  dimension "d2210" = 1.2
  dimension "d2211" = 4
  constraint horizontal L0
  constraint vertical L1
  constraint horizontal L2
  constraint vertical L3
  measures "d2208" horizontal distance of origin L0.start
  measures "d2209" vertical distance of origin L0.start
  measures "d2210" distance of L0.start L0.end
  measures "d2211" distance of L0.end L1.end
extrude "SW3 support 1 inclined cap" cut sketch "SW3 support 1 cap profile" along normal blind 39.0612 bodies 3
sketch "SW3 support 2 reinforced stem profile" plane through (0, 0, 2) normal (0, 0, 1) x (1, 0, 0)
  line L0 (65.8897, 20.0158) -> (68.2897, 20.0158)
  line L1 (68.2897, 20.0158) -> (68.2897, 25.0158)
  line L2 (68.2897, 25.0158) -> (65.8897, 25.0158)
  line L3 (65.8897, 25.0158) -> (65.8897, 20.0158)
  dimension "d2214" = 65.8897
  dimension "d2215" = 20.0158
  dimension "d2216" = 2.4
  dimension "d2217" = 5
  constraint horizontal L0
  constraint vertical L1
  constraint horizontal L2
  constraint vertical L3
  measures "d2214" horizontal distance of origin L0.start
  measures "d2215" vertical distance of origin L0.start
  measures "d2216" distance of L0.start L0.end
  measures "d2217" distance of L0.end L1.end
extrude "SW3 support 2 reinforced stem" add sketch "SW3 support 2 reinforced stem profile" along normal blind 11.7118 bodies 3
sketch "SW3 support 2 profile" plane through (0, 0, 2) normal (0, 0, 1) x (1, 0, 0)
  line L0 (66.5897, 21.0158) -> (67.5897, 21.0158)
  line L1 (67.5897, 21.0158) -> (67.5897, 24.0158)
  line L2 (67.5897, 24.0158) -> (66.5897, 24.0158)
  line L3 (66.5897, 24.0158) -> (66.5897, 21.0158)
  dimension "d2220" = 66.5897
  dimension "d2221" = 21.0158
  dimension "d2222" = 1
  dimension "d2223" = 3
  constraint horizontal L0
  constraint vertical L1
  constraint horizontal L2
  constraint vertical L3
  measures "d2220" horizontal distance of origin L0.start
  measures "d2221" vertical distance of origin L0.start
  measures "d2222" distance of L0.start L0.end
  measures "d2223" distance of L0.end L1.end
extrude "SW3 support 2" add sketch "SW3 support 2 profile" along normal blind 14.2118 bodies 3
sketch "SW3 support 2 cap profile" plane through (0, -1.1931, 13.6376) normal (0, -0.087156, 0.996195) x (1, 0, 0)
  line L0 (66.4897, 21.7995) -> (67.6897, 21.7995)
  line L1 (67.6897, 21.7995) -> (67.6897, 25.7995)
  line L2 (67.6897, 25.7995) -> (66.4897, 25.7995)
  line L3 (66.4897, 25.7995) -> (66.4897, 21.7995)
  dimension "d2226" = 66.4897
  dimension "d2227" = 21.7995
  dimension "d2228" = 1.2
  dimension "d2229" = 4
  constraint horizontal L0
  constraint vertical L1
  constraint horizontal L2
  constraint vertical L3
  measures "d2226" horizontal distance of origin L0.start
  measures "d2227" vertical distance of origin L0.start
  measures "d2228" distance of L0.start L0.end
  measures "d2229" distance of L0.end L1.end
extrude "SW3 support 2 inclined cap" cut sketch "SW3 support 2 cap profile" along normal blind 39.0612 bodies 3
sketch "SW4 receiver profile" plane through (0, -2.1431, 24.4961) normal (0, -0.087156, 0.996195) x (1, 0, 0)
  line L0 (6.3, 42.1972) -> (24.7, 42.1972)
  line L1 (24.7, 42.1972) -> (24.7, 59.7972)
  line L2 (24.7, 59.7972) -> (6.3, 59.7972)
  line L3 (6.3, 59.7972) -> (6.3, 42.1972)
  dimension "d2232" = 6.3
  dimension "d2233" = 42.1972
  dimension "d2234" = 18.4
  dimension "d2235" = 17.6
  constraint horizontal L0
  constraint vertical L1
  constraint horizontal L2
  constraint vertical L3
  measures "d2232" horizontal distance of origin L0.start
  measures "d2233" vertical distance of origin L0.start
  measures "d2234" distance of L0.start L0.end
  measures "d2235" distance of L0.end L1.end
extrude "SW4 integrated receiver" add sketch "SW4 receiver profile" against normal blind 11.5 bodies 2
sketch "SW4 switch lower clearance profile" plane through (0, -2.1431, 24.4961) normal (0, -0.087156, 0.996195) x (1, 0, 0)
  line L0 (7.5, 42.9972) -> (23.5, 42.9972)
  line L1 (23.5, 42.9972) -> (23.5, 58.9972)
  line L2 (23.5, 58.9972) -> (7.5, 58.9972)
  line L3 (7.5, 58.9972) -> (7.5, 42.9972)
  dimension "d2238" = 7.5
  dimension "d2239" = 42.9972
  dimension "d2240" = 16
  dimension "d2241" = 16
  constraint horizontal L0
  constraint vertical L1
  constraint horizontal L2
  constraint vertical L3
  measures "d2238" horizontal distance of origin L0.start
  measures "d2239" vertical distance of origin L0.start
  measures "d2240" distance of L0.start L0.end
  measures "d2241" distance of L0.end L1.end
extrude "SW4 switch lower clearance" cut sketch "SW4 switch lower clearance profile" against normal blind 5.5 bodies 2
sketch "SW4 holder pocket profile" plane through (0, -1.6638, 19.017) normal (0, -0.087156, 0.996195) x (1, 0, 0)
  line L0 (9.874, 44.425) -> (21.3055, 44.425)
  line L1 (21.3055, 44.425) -> (21.3055, 54.5741)
  line L2 (21.3055, 54.5741) -> (9.874, 54.5741)
  line L3 (9.874, 54.5741) -> (9.874, 44.425)
  dimension "d2244" = 9.874
  dimension "d2245" = 44.425
  dimension "d2246" = 11.4315
  dimension "d2247" = 10.1491
  constraint horizontal L0
  constraint vertical L1
  constraint horizontal L2
  constraint vertical L3
  measures "d2244" horizontal distance of origin L0.start
  measures "d2245" vertical distance of origin L0.start
  measures "d2246" distance of L0.start L0.end
  measures "d2247" distance of L0.end L1.end
extrude "SW4 open-bottom holder pocket" cut sketch "SW4 holder pocket profile" against normal blind 6.2 bodies 2
sketch "SW4 spring 1 release 1 profile" plane through (0, -2.056, 23.4999) normal (0, -0.087156, 0.996195) x (1, 0, 0)
  line L0 (6.2897, 51.5995) -> (9.874, 51.5995)
  line L1 (9.874, 51.5995) -> (9.874, 52.1995)
  line L2 (9.874, 52.1995) -> (6.2897, 52.1995)
  line L3 (6.2897, 52.1995) -> (6.2897, 51.5995)
  dimension "d2250" = 6.2897
  dimension "d2251" = 51.5995
  dimension "d2252" = 3.5843
  dimension "d2253" = 0.6
  constraint horizontal L0
  constraint vertical L1
  constraint horizontal L2
  constraint vertical L3
  measures "d2250" horizontal distance of origin L0.start
  measures "d2251" vertical distance of origin L0.start
  measures "d2252" distance of L0.start L0.end
  measures "d2253" distance of L0.end L1.end
extrude "SW4 spring 1 release 1" cut sketch "SW4 spring 1 release 1 profile" against normal blind 10.7 bodies 2
sketch "SW4 spring 1 release 2 profile" plane through (0, -2.056, 23.4999) normal (0, -0.087156, 0.996195) x (1, 0, 0)
  line L0 (6.2897, 54.1995) -> (9.874, 54.1995)
  line L1 (9.874, 54.1995) -> (9.874, 54.7995)
  line L2 (9.874, 54.7995) -> (6.2897, 54.7995)
  line L3 (6.2897, 54.7995) -> (6.2897, 54.1995)
  dimension "d2256" = 6.2897
  dimension "d2257" = 54.1995
  dimension "d2258" = 3.5843
  dimension "d2259" = 0.6
  constraint horizontal L0
  constraint vertical L1
  constraint horizontal L2
  constraint vertical L3
  measures "d2256" horizontal distance of origin L0.start
  measures "d2257" vertical distance of origin L0.start
  measures "d2258" distance of L0.start L0.end
  measures "d2259" distance of L0.end L1.end
extrude "SW4 spring 1 release 2" cut sketch "SW4 spring 1 release 2 profile" against normal blind 10.7 bodies 2
sketch "SW4 spring 1 inner clearance profile" plane through (0, -1.6638, 19.017) normal (0, -0.087156, 0.996195) x (1, 0, 0)
  line L0 (7.1897, 52.1995) -> (9.874, 52.1995)
  line L1 (9.874, 52.1995) -> (9.874, 54.1995)
  line L2 (9.874, 54.1995) -> (7.1897, 54.1995)
  line L3 (7.1897, 54.1995) -> (7.1897, 52.1995)
  dimension "d2262" = 7.1897
  dimension "d2263" = 52.1995
  dimension "d2264" = 2.6843
  dimension "d2265" = 2
  constraint horizontal L0
  constraint vertical L1
  constraint horizontal L2
  constraint vertical L3
  measures "d2262" horizontal distance of origin L0.start
  measures "d2263" vertical distance of origin L0.start
  measures "d2264" distance of L0.start L0.end
  measures "d2265" distance of L0.end L1.end
extrude "SW4 spring 1 inner clearance" cut sketch "SW4 spring 1 inner clearance profile" against normal blind 6.2 bodies 2
sketch "SW4 spring 1 hook profile" plane through (0, -1.2106, 13.8368) normal (0, -0.087156, 0.996195) x (1, 0, 0)
  line L0 (6.3897, 52.1995) -> (10.374, 52.1995)
  line L1 (10.374, 52.1995) -> (10.374, 54.1995)
  line L2 (10.374, 54.1995) -> (6.3897, 54.1995)
  line L3 (6.3897, 54.1995) -> (6.3897, 52.1995)
  dimension "d2268" = 6.3897
  dimension "d2269" = 52.1995
  dimension "d2270" = 3.9843
  dimension "d2271" = 2
  constraint horizontal L0
  constraint vertical L1
  constraint horizontal L2
  constraint vertical L3
  measures "d2268" horizontal distance of origin L0.start
  measures "d2269" vertical distance of origin L0.start
  measures "d2270" distance of L0.start L0.end
  measures "d2271" distance of L0.end L1.end
extrude "SW4 spring 1 retaining hook" add sketch "SW4 spring 1 hook profile" against normal blind 0.8 bodies 2
chamfer "SW4 spring 1 45 degree lead-in" distance 0.35 angle 45 1 edges at (10.374, 51.8562, 17.6765) tangent chain off on bodies 2
sketch "SW4 spring 2 release 1 profile" plane through (0, -2.056, 23.4999) normal (0, -0.087156, 0.996195) x (1, 0, 0)
  line L0 (21.3055, 51.5995) -> (24.8897, 51.5995)
  line L1 (24.8897, 51.5995) -> (24.8897, 52.1995)
  line L2 (24.8897, 52.1995) -> (21.3055, 52.1995)
  line L3 (21.3055, 52.1995) -> (21.3055, 51.5995)
  dimension "d2275" = 21.3055
  dimension "d2276" = 51.5995
  dimension "d2277" = 3.5843
  dimension "d2278" = 0.6
  constraint horizontal L0
  constraint vertical L1
  constraint horizontal L2
  constraint vertical L3
  measures "d2275" horizontal distance of origin L0.start
  measures "d2276" vertical distance of origin L0.start
  measures "d2277" distance of L0.start L0.end
  measures "d2278" distance of L0.end L1.end
extrude "SW4 spring 2 release 1" cut sketch "SW4 spring 2 release 1 profile" against normal blind 10.7 bodies 2
sketch "SW4 spring 2 release 2 profile" plane through (0, -2.056, 23.4999) normal (0, -0.087156, 0.996195) x (1, 0, 0)
  line L0 (21.3055, 54.1995) -> (24.8897, 54.1995)
  line L1 (24.8897, 54.1995) -> (24.8897, 54.7995)
  line L2 (24.8897, 54.7995) -> (21.3055, 54.7995)
  line L3 (21.3055, 54.7995) -> (21.3055, 54.1995)
  dimension "d2281" = 21.3055
  dimension "d2282" = 54.1995
  dimension "d2283" = 3.5843
  dimension "d2284" = 0.6
  constraint horizontal L0
  constraint vertical L1
  constraint horizontal L2
  constraint vertical L3
  measures "d2281" horizontal distance of origin L0.start
  measures "d2282" vertical distance of origin L0.start
  measures "d2283" distance of L0.start L0.end
  measures "d2284" distance of L0.end L1.end
extrude "SW4 spring 2 release 2" cut sketch "SW4 spring 2 release 2 profile" against normal blind 10.7 bodies 2
sketch "SW4 spring 2 inner clearance profile" plane through (0, -1.6638, 19.017) normal (0, -0.087156, 0.996195) x (1, 0, 0)
  line L0 (21.3055, 52.1995) -> (23.9897, 52.1995)
  line L1 (23.9897, 52.1995) -> (23.9897, 54.1995)
  line L2 (23.9897, 54.1995) -> (21.3055, 54.1995)
  line L3 (21.3055, 54.1995) -> (21.3055, 52.1995)
  dimension "d2287" = 21.3055
  dimension "d2288" = 52.1995
  dimension "d2289" = 2.6843
  dimension "d2290" = 2
  constraint horizontal L0
  constraint vertical L1
  constraint horizontal L2
  constraint vertical L3
  measures "d2287" horizontal distance of origin L0.start
  measures "d2288" vertical distance of origin L0.start
  measures "d2289" distance of L0.start L0.end
  measures "d2290" distance of L0.end L1.end
extrude "SW4 spring 2 inner clearance" cut sketch "SW4 spring 2 inner clearance profile" against normal blind 6.2 bodies 2
sketch "SW4 spring 2 hook profile" plane through (0, -1.2106, 13.8368) normal (0, -0.087156, 0.996195) x (1, 0, 0)
  line L0 (20.8055, 52.1995) -> (24.7897, 52.1995)
  line L1 (24.7897, 52.1995) -> (24.7897, 54.1995)
  line L2 (24.7897, 54.1995) -> (20.8055, 54.1995)
  line L3 (20.8055, 54.1995) -> (20.8055, 52.1995)
  dimension "d2293" = 20.8055
  dimension "d2294" = 52.1995
  dimension "d2295" = 3.9843
  dimension "d2296" = 2
  constraint horizontal L0
  constraint vertical L1
  constraint horizontal L2
  constraint vertical L3
  measures "d2293" horizontal distance of origin L0.start
  measures "d2294" vertical distance of origin L0.start
  measures "d2295" distance of L0.start L0.end
  measures "d2296" distance of L0.end L1.end
extrude "SW4 spring 2 retaining hook" add sketch "SW4 spring 2 hook profile" against normal blind 0.8 bodies 2
chamfer "SW4 spring 2 45 degree lead-in" distance 0.35 angle 45 1 edges at (20.8055, 51.8562, 17.6765) tangent chain off on bodies 2